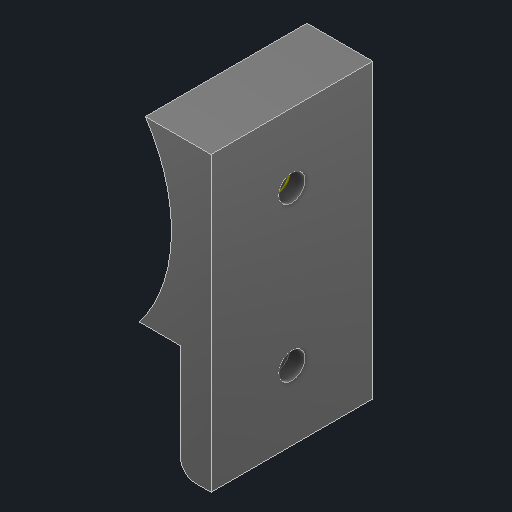
# Autodesk Inventor part: Suporte motor Pittman
Saved by Autodesk Inventor 2026.1 (Build 301233000, 233)
## iProperties
Created: 2025-01-07
Part Number: Suporte motor Pittman
Material: ABS plástico
Document SubType Name: Modeling
Designer: Cliente
Density: 1.00912 g/cm^3
Appearance: Suave - Branco
Mass: 4.19 g
Surface Area: 25.0842 cm^2
Volume: 4.15214 cm^3
Author: Cliente
Autodesk Inventor part; units mm, degrees
ref_plane "YZ Plane" through (0, 0, 0) normal (1, 0, 0) x (0, 1, 0)
ref_plane "XZ Plane" through (0, 0, 0) normal (0, 1, 0) x (-1, 0, 0)
ref_plane "Plano de trabalho1" through (0, 0, 0) normal (0, 0, 1) x (1, 0, 0)
sketch "Esboço1" plane through (0, 0, 0) normal (0, 0, 1) x (1, 0, 0)
  line L0 (45.35, 7) -> (45.35, 11.7) projected
  arc A0 (45.35, 11.7) -> (44.85, 12.2) centre (44.85, 11.7) ccw projected
  line L1 (44.85, 12.2) -> (40.15, 12.2) projected
  line L2 (40.15, 12.2) -> (38.35, 10.4) projected
  line L3 (38.35, 10.4) -> (40.85, 10.4) projected
  line L4 (40.85, 10.4) -> (40.85, 8.6899) projected
  line L5 (40.85, 8.6899) -> (38.3601, 6.2) projected
  line L6 (38.3601, 6.2) -> (32.3399, 6.2) projected
  line L7 (32.3399, 6.2) -> (29.85, 8.6899) projected
  line L8 (29.85, 8.6899) -> (29.85, 10.4) projected
  line L9 (29.85, 10.4) -> (32.35, 10.4) projected
  line L10 (32.35, 10.4) -> (30.55, 12.2) projected
  line L11 (30.55, 12.2) -> (25.85, 12.2) projected
  arc A1 (25.85, 12.2) -> (25.35, 11.7) centre (25.85, 11.7) ccw projected
  line L12 (25.35, 11.7) -> (25.35, 7) projected
  line L13 (25.35, 7) -> (27.15, 5.2) projected
  line L14 (27.15, 5.2) -> (27.15, 7.7) projected
  line L15 (27.15, 7.7) -> (28.8601, 7.7) projected
  line L16 (28.8601, 7.7) -> (31.35, 5.2101) projected
  line L17 (31.35, 5.2101) -> (31.35, -0.8101) projected
  line L18 (31.35, -0.8101) -> (28.8601, -3.3) projected
  line L19 (28.8601, -3.3) -> (27.15, -3.3) projected
  line L20 (27.15, -3.3) -> (27.15, -0.8) projected
  line L21 (27.15, -0.8) -> (25.35, -2.6) projected
  line L22 (25.35, -2.6) -> (25.35, -13) projected
  line L23 (25.35, -13) -> (27.15, -14.8) projected
  line L24 (27.15, -14.8) -> (27.15, -12.3) projected
  line L25 (27.15, -12.3) -> (28.8601, -12.3) projected
  line L26 (28.8601, -12.3) -> (31.35, -14.7899) projected
  line L27 (31.35, -14.7899) -> (31.35, -20.8101) projected
  line L28 (31.35, -20.8101) -> (28.8601, -23.3) projected
  line L29 (28.8601, -23.3) -> (27.15, -23.3) projected
  line L30 (27.15, -23.3) -> (27.15, -20.8) projected
  line L31 (27.15, -20.8) -> (25.35, -22.6) projected
  line L32 (25.35, -22.6) -> (25.35, -27.3) projected
  arc A2 (25.35, -27.3) -> (25.85, -27.8) centre (25.85, -27.3) ccw projected
  line L33 (25.85, -27.8) -> (30.55, -27.8) projected
  line L34 (30.55, -27.8) -> (32.35, -26) projected
  line L35 (32.35, -26) -> (29.85, -26) projected
  line L36 (29.85, -26) -> (29.85, -24.2899) projected
  line L37 (29.85, -24.2899) -> (32.3399, -21.8) projected
  line L38 (32.3399, -21.8) -> (38.3601, -21.8) projected
  line L39 (38.3601, -21.8) -> (40.85, -24.2899) projected
  line L40 (40.85, -24.2899) -> (40.85, -26) projected
  line L41 (40.85, -26) -> (38.35, -26) projected
  line L42 (38.35, -26) -> (40.15, -27.8) projected
  line L43 (40.15, -27.8) -> (44.85, -27.8) projected
  arc A3 (44.85, -27.8) -> (45.35, -27.3) centre (44.85, -27.3) ccw projected
  line L44 (45.35, -27.3) -> (45.35, -22.6) projected
  line L45 (45.35, -22.6) -> (43.55, -20.8) projected
  line L46 (43.55, -20.8) -> (43.55, -23.3) projected
  line L47 (43.55, -23.3) -> (41.8399, -23.3) projected
  line L48 (41.8399, -23.3) -> (39.35, -20.8101) projected
  line L49 (39.35, -20.8101) -> (39.35, -14.7899) projected
  line L50 (39.35, -14.7899) -> (41.8399, -12.3) projected
  line L51 (41.8399, -12.3) -> (43.55, -12.3) projected
  line L52 (43.55, -12.3) -> (43.55, -14.8) projected
  line L53 (43.55, -14.8) -> (45.35, -13) projected
  line L54 (45.35, -13) -> (45.35, -2.6) projected
  line L55 (45.35, -2.6) -> (43.55, -0.8) projected
  line L56 (43.55, -0.8) -> (43.55, -3.3) projected
  line L57 (43.55, -3.3) -> (41.8399, -3.3) projected
  line L58 (41.8399, -3.3) -> (39.35, -0.8101) projected
  line L59 (39.35, -0.8101) -> (39.35, 5.2101) projected
  line L60 (39.35, 5.2101) -> (41.8399, 7.7) projected
  line L61 (41.8399, 7.7) -> (43.55, 7.7) projected
  line L62 (43.55, 7.7) -> (43.55, 5.2) projected
  line L63 (43.55, 5.2) -> (45.35, 7) projected
  circle A4 centre (35.35, 2.2) radius 2.5 projected
  circle A5 centre (35.35, -17.8) radius 2.5 projected
  line L64 (27.15, -10.9) -> (27.15, -4.7) projected
  line L65 (27.15, -4.7) -> (29.4399, -4.7) projected
  line L66 (29.4399, -4.7) -> (32.3399, -1.8) projected
  line L67 (32.3399, -1.8) -> (38.3601, -1.8) projected
  line L68 (38.3601, -1.8) -> (41.2601, -4.7) projected
  line L69 (41.2601, -4.7) -> (43.55, -4.7) projected
  line L70 (43.55, -4.7) -> (43.55, -10.9) projected
  line L71 (43.55, -10.9) -> (41.2601, -10.9) projected
  line L72 (41.2601, -10.9) -> (38.3601, -13.8) projected
  line L73 (38.3601, -13.8) -> (32.3399, -13.8) projected
  line L74 (32.3399, -13.8) -> (29.4399, -10.9) projected
  line L75 (29.4399, -10.9) -> (27.15, -10.9) projected
  circle A6 centre (0, 0) radius 20 projected
  line L76 (23.35, -26.8) -> (25.35, -26.8)
  line L77 (25.35, -26.8) -> (25.35, 11.2)
  line L78 (25.35, 11.2) -> (21.35, 11.2)
  line L79 (21.35, 11.2) -> (21.35, -24.8)
  line L80 (21.35, -26.8) -> (25.35, 11.2) construction
  line L81 (25.35, -26.8) -> (21.35, 11.2) construction
  circle A7 centre (0, 0) radius 20.2
  line L82 (21.35, 11.2) -> (16.8107, 11.2)
  line L83 (21.35, -12.3) -> (16.0234, -12.3)
  arc A8 (21.35, -24.8) -> (23.35, -26.8) centre (23.35, -24.8) ccw
  point P0 (0, 0)
  point P1 (23.35, -7.8)
  point P2 (25.35, -7.8)
  point P3 (25.35, -26.8)
  point P4 (25.35, -13)
  point P5 (25.35, -22.6)
  point P6 (25.35, 7)
  point P7 (25.35, -2.6)
  point P8 (18.236, -8.6885)
  point P9 (14.236, -14.331)
  point P10 (19.3118, 5.9242)
  point P11 (20.036, -2.5691)
  point P12 (16.8107, 11.2)
  point P13 (18.236, 8.6885)
  dimension "d0" = 4
  dimension "d1" = 38
  dimension "d2" = 0.2
  dimension "d10" = 2
  constraints: 16 end point, 4 point on circle, 4 point on line, 3 horizontal, 3 midpoint, 2 centre point, 2 horizontal alignment, 2 parallel, 2 tangent, 1 perpendicular
  measures "d0" distance of L78.end L77.end
  measures "d1" distance of L77.end L76.end
  measures "d2" radial gap between concentric circles of A6 A7
  measures "d10" radius of A8
extrude "Extrusão1" add sketch "Esboço1" along normal mid plane 21 contours L12 L77 L22 L32 L76 A8 L79 L78 | L79 L83 A7 L82
sketch "Esboço2" plane through (25.35, -26.8, 15) normal (1, 0, 0) x (0, 0, -1)
  line L0 (25.5, 38) -> (4.5, 38) projected
  line L1 (4.5, 0) -> (4.5, 38) projected
  line L2 (25.5, 38) -> (25.5, 0) projected
  line L3 (15, 9) -> (15, 29)
  circle A0 centre (15, 29) radius 1.7
  circle A1 centre (15, 9) radius 1.7
  line L4 (25.5, 0) -> (4.5, 0) projected
  point P0 (15, 26.8)
  point P1 (15, 19)
  point P2 (4.5, 19)
  point P3 (15, 38)
  dimension "d5" = 20
  dimension "d6" = 3.4
  dimension "d7" = 3.4
  constraints: 3 midpoint, 2 centre point, 2 coincident, 2 end point, 1 horizontal alignment, 1 vertical, 1 vertical alignment
  measures "d5" distance of L3.start L3.end
  measures "d6" diameter of A0
  measures "d7" diameter of A1
extrude "Extrusão2" cut sketch "Esboço2" against normal through all contours A0 | A1
sketch "Esboço3" plane through (21.35, -24.8, 10.5) normal (-1, 0, 0) x (0, 0, 1)
  circle A0 centre (-10.5, 27) radius 1.7 projected
  circle A1 centre (-10.5, 7) radius 1.7 projected
  circle A2 centre (-10.5, 7) radius 3.025
  circle A3 centre (-10.5, 27) radius 3.025
  point P0 (-10.5, 24.8)
  dimension "d11" = 6.05
  dimension "d12" = 6.05
  constraints: 2 centre point, 2 coincident
  measures "d11" diameter of A2
  measures "d12" diameter of A3
extrude "Extrusão3" cut sketch "Esboço3" along normal blind 10 and the other way blind 2
sketch "Esboço4" plane through (23.35, 2.2, 0) normal (-1, 0, 0) x (0, 0, 1)
  circle A0 centre (0, 0) radius 1.7 projected
  circle A1 centre (0, 0) radius 3.025 projected
  circle A2 centre (0, 0) radius 1.7 projected
  point P0 (0, -2.2)
